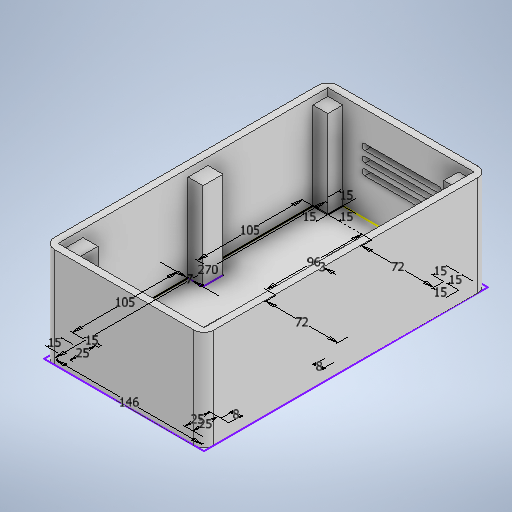
# Autodesk Inventor part: Part1
Saved by Autodesk Inventor 2025.2 (Build 292293000, 293)
## iProperties
Created: 2025-02-20
Part Number: Part1
Material: Generic
Document SubType Name: Modeling
Designer: Marcos
Density: 1 g/cm^3
Appearance: Default
Author: Marcos
Autodesk Inventor part; units mm, degrees
ref_plane "YZ Plane" through (0, 0, 0) normal (1, 0, 0) x (0, 1, 0)
ref_plane "XZ Plane" through (0, 0, 0) normal (0, 1, 0) x (-1, 0, 0)
ref_plane "XY Plane" through (0, 0, 0) normal (0, 0, 1) x (1, 0, 0)
sketch "Sketch1" plane through (0, 0, 0) normal (0, 1, 0) x (-1, 0, 0)
  line L0 (-74, -135) -> (72, -135)
  line L1 (72, -135) -> (72, 135)
  line L2 (72, 135) -> (-74, 135)
  line L3 (-74, 135) -> (-74, -135)
  line L4 (79, 142) -> (79, -142)
  line L5 (79, -142) -> (-81, -142)
  line L6 (-81, -142) -> (-81, 142)
  line L7 (-81, 142) -> (79, 142)
  point P0 (0, 0)
  dimension "d0" = 146
  dimension "d1" = 270
  dimension "d2" = 7
  constraints: 16 end point, 4 parallel, 2 perpendicular, 1 horizontal, 3 other
  measures "d0" distance of L2.end L1.end
  measures "d1" distance of L0.end L1.end
  measures "d2" distance between parallel lines of L1 L4
extrude "Extrusion1" add sketch "Sketch1" along normal blind 5 contours L3 L2 L1 L0
extrude "Extrusion2" add sketch "Sketch1" along normal blind 100
sketch "Sketch2" plane through (81, 0, -142) normal (0, 0, -1) x (-1, 0, 0)
  point P0 (81, 0)
sketch "Sketch3" plane through (81, 0, -142) normal (0, 0, -1) x (-1, 0, 0)
  line L0 (0, 0) -> (0, 100) projected
  line L1 (160, 0) -> (160, 100) projected
  line L2 (39, 70) -> (119, 70)
  line L3 (39, 70) -> (39, 64)
  line L4 (39, 59) -> (39, 53)
  line L5 (39, 48) -> (39, 42)
  line L6 (39, 70) -> (119, 70)
  line L7 (119, 70) -> (119, 64)
  line L8 (119, 64) -> (39, 64)
  line L9 (39, 64) -> (39, 70)
  line L10 (39, 59) -> (119, 59)
  line L11 (119, 59) -> (119, 53)
  line L12 (119, 53) -> (39, 53)
  line L13 (39, 53) -> (39, 59)
  line L14 (39, 48) -> (119, 48)
  line L15 (119, 48) -> (119, 42)
  line L16 (119, 42) -> (39, 42)
  line L17 (39, 42) -> (39, 48)
  point P0 (81, 0)
  point P1 (79, 50)
  dimension "d9" = 6
  dimension "d10" = 5
  dimension "d11" = 6
  dimension "d12" = 5
  dimension "d13" = 6
  constraints: 32 end point, 6 parallel, 4 horizontal, 3 perpendicular
  measures "d9" distance of L2.start L3.end
  measures "d10" distance of L3.end L4.start
  measures "d11" distance of L4.start L4.end
  measures "d12" distance of L4.end L5.start
  measures "d13" distance of L5.start L5.end
extrude "Extrusion3" cut sketch "Sketch3" against normal blind 100
fillet "Fillet1" radius 3 12 edges at (42, 70, -138.5) (42, 59, -138.5) (42, 48, -138.5) (-38, 48, -138.5) (-38, 59, -138.5) (-38, 70, -138.5) (-38, 42, -138.5) (-38, 53, -138.5) (-38, 64, -138.5) (42, 42, -138.5) (42, 53, -138.5) (42, 64, -138.5)
sketch "Sketch4" plane through (0, 5, 0) normal (0, 1, 0) x (1, 0, 0)
  line L0 (-72, 135) -> (74, 135) projected
  line L1 (74, 135) -> (74, 120)
  line L2 (74, 135) -> (74, -135) projected
  line L3 (74, 120) -> (59, 120)
  line L4 (59, 120) -> (59, 135)
  line L5 (-57, 135) -> (-57, 120)
  line L6 (-57, 120) -> (-72, 120)
  line L7 (-72, 135) -> (-72, -135) projected
  line L8 (74, -135) -> (74, -110)
  line L9 (74, -110) -> (66, -110)
  line L10 (66, -110) -> (66, -135)
  line L11 (59, 120) -> (-57, 120) construction
  line L12 (59, 120) -> (59, 0) construction
  line L13 (59, 120) -> (-13, 120)
  line L14 (-13, 120) -> (-13, 24)
  line L15 (-13, 24) -> (59, 24)
  line L16 (59, 24) -> (59, 120)
  line L17 (-16, 21) -> (-16, 123)
  line L18 (-16, 123) -> (62, 123)
  line L19 (62, 123) -> (62, 21)
  line L20 (62, 21) -> (-16, 21)
  line L21 (62, 120) -> (59, 120)
  line L22 (74, -135) -> (-72, -135) projected
  line L23 (-42, -135) -> (-72, -135)
  line L24 (-72, -135) -> (-72, -120)
  line L25 (74, -110) -> (74, -135)
  line L26 (74, -135) -> (66, -135)
  line L27 (59, 135) -> (74, 135)
  line L28 (74, 120) -> (59, 120)
  line L29 (-72, 120) -> (-72, 135)
  line L30 (-57, -135) -> (-57, -110)
  line L31 (-57, -110) -> (-72, -110)
  line L32 (-72, -110) -> (-72, -5)
  line L33 (-72, 120) -> (-72, 15)
  line L34 (-72, -5) -> (-72, 15)
  line L35 (-57, 15) -> (-57, -5)
  line L36 (-57, -5) -> (-72, -5)
  line L37 (-57, 15) -> (-72, 15)
  line L38 (-72, -5) -> (-72, 15)
  line L39 (74, -5) -> (66, -5)
  line L40 (66, -5) -> (66, 15)
  line L41 (66, 15) -> (74, 15)
  line L42 (74, -5) -> (74, 15)
  point P0 (0, 0)
  point P1 (59, 123)
  dimension "d18" = 15
  dimension "d19" = 15
  dimension "d20" = 15
  dimension "d21" = 15
  dimension "d22" = 15
  dimension "d23" = 15
  dimension "d24" = 15
  dimension "d27" = 25
  dimension "d28" = 8
  dimension "d29" = 25
  dimension "d30" = 72
  dimension "d31" = 96
  dimension "d32" = 72
  dimension "d33" = 3
  dimension "d38" = 25
  dimension "d39" = 15
  dimension "d42" = 105
  dimension "d43" = 105
  dimension "d44" = 8
  constraints: 78 end point, 13 point on line, 12 perpendicular, 6 collinear, 3 horizontal, 3 vertical, 1 midpoint, 3 other
  measures "d18" distance of L0.end L1.end
  measures "d19" distance of L1.end L3.end
  measures "d20" distance of L3.end L4.end
  measures "d21" distance of L0.start L5.start
  measures "d22" distance of L5.start L5.end
  measures "d23" distance of L5.end L6.end
  measures "d24" distance of L7.end L24.end
  measures "d27" distance of L2.end L8.end
  measures "d28" distance of L8.end L9.end
  measures "d29" distance of L9.end L10.end
  measures "d30" distance of L3.end L13.end
  measures "d31" distance of L13.end L14.end
  measures "d32" distance of L14.end L15.end
  measures "d33" distance between parallel lines of L14 L17
  measures "d38" distance of L30.start L30.end
  measures "d39" distance of L30.end L31.end
  measures "d42" distance of L31.end L32.end
  measures "d43" distance of L6.end L33.end
  measures "d44" distance of L39.start L39.end
extrude "Extrusion4" add sketch "Sketch4" along normal blind 4 contours L4 L3 L19 L20 L17 L18
extrude "Extrusion6" add sketch "Sketch4" along normal blind 87.5 contours L0 L5 L6 L7 | L0 L1 L3 L19 L18 L4 | L37 L35 L36 L7 | L18 L19 L3 L4 | L31 L30 L22 L7 | L2 L39 L40 L41 | L2 L22 L10 L9
fillet "Fillet2" radius 10 4 edges at (81, 50, 142) (81, 50, -142) (-79, 50, -142) (-79, 50, 142)
body "Solid1"
